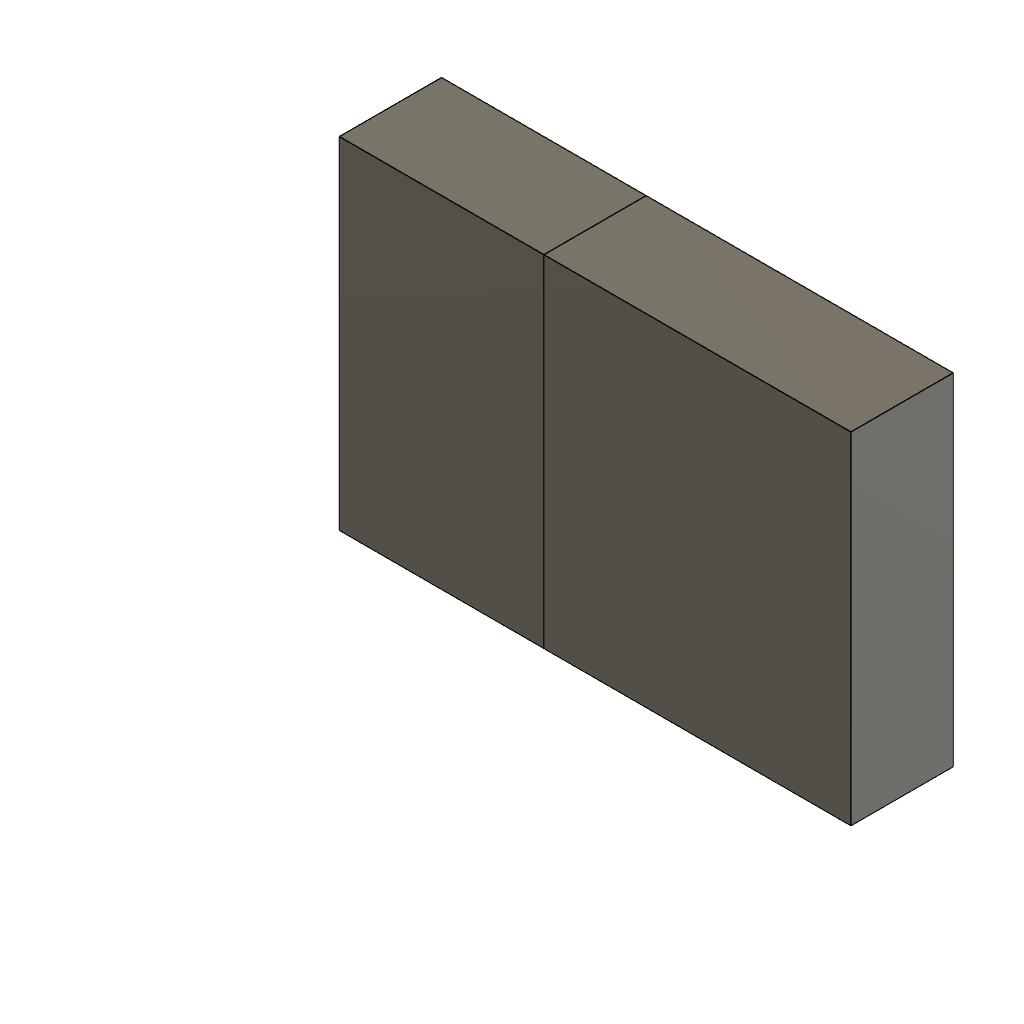
split_body_plane_yz (Autodesk Fusion 360 design; units mm, degrees)
part number: 2026-11-13-14-47-28-634
Autodesk Fusion 360 part; units mm, degrees
sketch "Sketch1" plane through (0, 0, 0) normal (0, 0, 1) x (1, 0, 0)
  line L0 (0, 0) -> (30, 0)
  line L1 (30, 0) -> (30, 20)
  line L2 (30, 20) -> (0, 20)
  line L3 (0, 20) -> (0, 0)
extrude "Extrude1" add sketch "Sketch1" along normal blind 6 makes body 1
ref_plane "WorkPlane1" through (12, 0, 0) normal (1, 0, 0) x (0, 1, 0)
split "Split1" by plane through (12, 0, 0) normal (1, 0, 0) bodies 1 makes body 2 at (18, 13.3333, 0)
